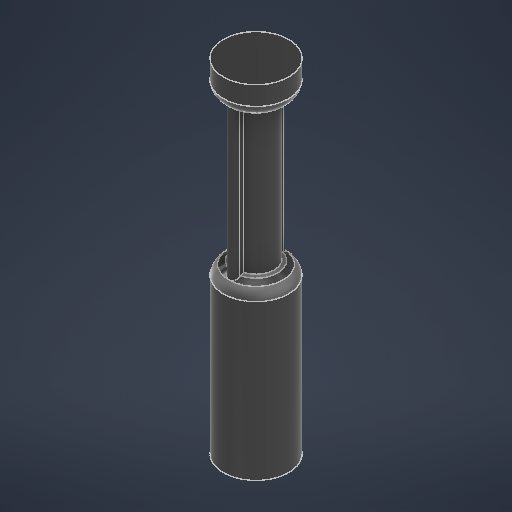
# Autodesk Inventor part: Endcap
Saved by Autodesk Inventor 2026.2 (Build 302298010, 298A)
## iProperties
Created: 2026-05-07
Part Number: Endcap
Material: PBT 플라스틱
Document SubType Name: Modeling
Designer: work
Density: 1.31 g/cm^3
Appearance: 섬세 텍스처 - 검은색
Author: work
Autodesk Inventor part; units mm, degrees
ref_plane "YZ Plane" through (0, 0, 0) normal (1, 0, 0) x (0, 1, 0)
ref_plane "XZ Plane" through (0, 0, 0) normal (0, 1, 0) x (-1, 0, 0)
sketch "스케치1" plane through (0, 0, 0) normal (0, 1, 0) x (-1, 0, 0)
  circle A0 centre (0, 0) radius 3
  dimension "d0" = 6
  constraints: 1 centre point, 1 coincident
  measures "d0" diameter of A0
extrude "돌출1" add sketch "스케치1" along normal blind 31.5
sketch "스케치2" plane through (0, 0, 0) normal (0, -1, 0) x (1, 0, 0)
  circle A0 centre (0, 0) radius 1.5
  dimension "d3" = 3
  constraints: 1 centre point, 1 coincident
  measures "d3" diameter of A0
extrude "돌출2" cut sketch "스케치2" against normal blind 12
ref_plane "작업 평면1" through (0, 28.5, 0) normal (0, 1, 0) x (1, 0, 0)
sketch "스케치3" plane through (0, 28.5, 0) normal (0, 1, 0) x (1, 0, 0)
  circle A0 centre (0, 0) radius 1.7
  circle A1 centre (0, 0) radius 1.5 projected
  circle A2 centre (0, 0) radius 3 projected
  line L0 (-0.5, -2.5) -> (0.5, -2.5)
  line L1 (0.5, -2.5) -> (0.5, 2.5)
  line L2 (0.5, 2.5) -> (-0.5, 2.5)
  line L3 (-0.5, 2.5) -> (-0.5, -2.5)
  line L4 (-0.5, -2.5) -> (0.5, 2.5) construction
  line L5 (0.5, -2.5) -> (-0.5, 2.5) construction
  point P0 (-0.5, -1.6248)
  point P1 (-0.5, 1.6248)
  point P2 (0.5, 1.6248)
  point P3 (0.5, -1.6248)
  dimension "d7" = 3.4
  dimension "d10" = 1
  dimension "d11" = 5
  constraints: 12 end point, 2 midpoint, 2 parallel, 1 centre point, 1 coincident, 1 horizontal, 1 perpendicular
  measures "d7" diameter of A0
  measures "d10" distance of L2.end L1.end
  measures "d11" distance of L1.end L0.end
extrude "돌출3" cut sketch "스케치3" against normal blind 13
fillet "모깎기1" radius 0.5 4 edges at (0.5, 22, 2.5) (-0.5, 22, 2.5) (0.5, 22, -2.5) (-0.5, 22, -2.5)
chamfer "모따기1" distance 1.2 angle 30 1 edges at (3, 28.5, 0)
chamfer "모따기2" distance 1.2 angle 30 1 edges at (3, 15.5, 0)
fillet "모깎기2" radius 1 8 edges at (3, 14.8072, 0) (3, 29.1928, 0) (-1.4387, 28.5, 1.0817) (-1.4387, 28.5, -1.0817) (-1.4387, 15.5, 1.0817) (-1.4387, 15.5, -1.0817) (1.8, 15.5, 0) (1.8, 28.5, 0)
